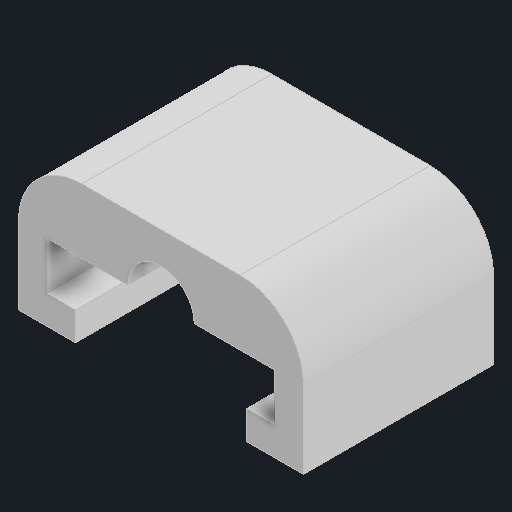
# Autodesk Inventor part: Tapa eje ABD
Saved by Autodesk Inventor 2026 (Build 300175050, 175E)
## iProperties
Created: 2026-05-09
Part Number: Tapa eje ABD
Material: Genérico
Document SubType Name: Modeling
Designer: thepr
Density: 1 g/cm^3
Appearance: Valor por defecto
Author: thepr
## iProperties of the stored document _3DPrint.ipt
Created: 2026-06-08
Part Number: _3DPrint
Material: Genérico
Document SubType Name: Modeling
Designer: thepr
Density: 1 g/cm^3
Appearance: Valor por defecto
Author: thepr
Autodesk Inventor part; units mm, degrees
ref_plane "YZ Plane" through (0, 0, 0) normal (1, 0, 0) x (0, 1, 0)
ref_plane "XZ Plane" through (0, 0, 0) normal (0, 1, 0) x (-1, 0, 0)
ref_plane "XY Plane" through (0, 0, 0) normal (0, 0, 1) x (1, 0, 0)
sketch "Boceto1" plane through (0, 0, 0) normal (0, 0, 1) x (1, 0, 0)
  circle A0 centre (0, 0) radius 2.1
  line L0 (-9, 0) -> (9, 0)
  line L1 (9, 0) -> (9, 4.1)
  line L2 (9, 4.1) -> (-9, 4.1)
  line L3 (-9, 4.1) -> (-9, 0)
  line L4 (-9, 0) -> (-9, -4.8)
  line L5 (-9, -4.8) -> (-5.4, -4.8)
  line L6 (-5.4, -4.8) -> (-5.4, -3)
  line L7 (-5.4, -3) -> (-7.2, -3)
  line L8 (-7.2, -3) -> (-7.2, 0)
  line L9 (9, 0) -> (9, -4.8)
  line L10 (9, -4.8) -> (5.4, -4.8)
  line L11 (5.4, -4.8) -> (5.4, -3)
  line L12 (5.4, -3) -> (7.2, -3)
  line L13 (7.2, -3) -> (7.2, 0)
  point P0 (-2.1, 0)
  point P1 (2.1, 0)
  dimension "d0" = 4.2
  dimension "d1" = 2
  dimension "d2" = 18
  dimension "d3" = 1.8
  dimension "d4" = 1.8
  dimension "d5" = 3
  dimension "d6" = 1.8
  dimension "d7" = 1.8
  dimension "d8" = 1.8
  constraints: 28 end point, 7 perpendicular, 6 point on line, 3 parallel, 2 coincident, 1 centre point, 1 horizontal, 1 midpoint, 1 vertical
  measures "d0" diameter of A0
  measures "d1" distance edge to line of A0 L2
  measures "d2" distance between parallel lines of L1 L3
  measures "d3" distance between parallel lines of L4 L8
  measures "d4" distance between parallel lines of L9 L13
  measures "d5" distance between parallel lines of L7 L0
  measures "d6" distance between parallel lines of L5 L7
  measures "d7" distance between parallel lines of L8 L6
  measures "d8" distance between parallel lines of L13 L11
extrude "Extrusión1" add sketch "Boceto1" along normal blind 12 contours A0 L0 L3 L2 L1 | L0 L9 L10 L11 L12 L13 | L8 L7 L6 L5 L4 L0
fillet "Empalme1" radius 4 2 edges at (-9, 4.1, 6) (9, 4.1, 6)
